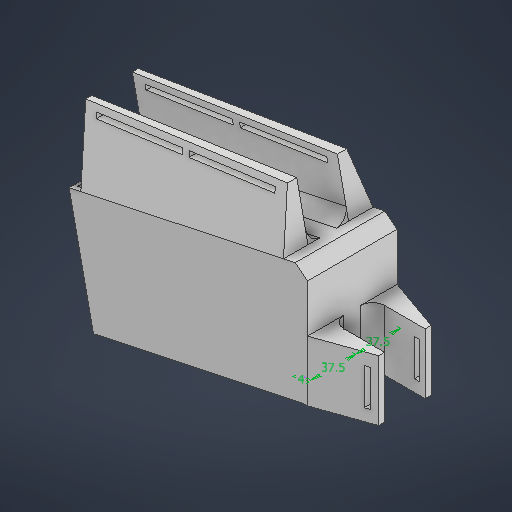
# Autodesk Inventor part: controllerholder
Saved by Autodesk Inventor 2026.3 (Build 303398000, 398)
## iProperties
Created: 2026-03-26
Part Number: controllerholder
Material: Generic
Document SubType Name: Modeling
Designer: runek
Density: 1 g/cm^3
Appearance: Default
Author: runek
Autodesk Inventor part; units mm, degrees
ref_plane "YZ Plane" through (0, 0, 0) normal (1, 0, 0) x (0, 1, 0)
ref_plane "XZ Plane" through (0, 0, 0) normal (0, 1, 0) x (-1, 0, 0)
ref_plane "XY Plane" through (0, 0, 0) normal (0, 0, 1) x (1, 0, 0)
sketch "Sketch1" plane through (0, 0, 0) normal (0, 1, 0) x (-1, 0, 0)
  line L0 (17.5, 0) -> (17.5, -37.5)
  line L1 (17.5, 0) -> (17.5, 37.5)
  line L2 (17.5, -37.5) -> (21.5, -37.5)
  line L3 (21.5, -37.5) -> (21.5, 37.5)
  line L4 (21.5, 37.5) -> (17.5, 37.5)
  line L5 (17.5, 37.5) -> (17.5, -37.5)
  point P0 (0, 0)
  point P1 (17.5, 37.5)
  dimension "d8" = 37.5
  dimension "d9" = 37.5
  dimension "d10" = 4
  constraints: 12 end point, 2 parallel, 1 horizontal, 1 perpendicular, 1 point on line, 1 vertical
  measures "d8" distance of L0.start L0.end
  measures "d9" distance of L0.start L1.end
  measures "d10" distance of L4.end L3.end
extrude "Extrusion2" add sketch "Sketch1" along normal blind 80
extrude "Extrusion3" add sketch "Sketch1" against normal blind 20
sketch "Sketch4" plane through (-17.5, 80, -37.5) normal (0, 0, -1) x (-1, 0, 0)
  line L0 (0, 0) -> (4, 0) projected
  line L1 (4, 0) -> (199.6295, -41.5823)
  line L2 (4, 0) -> (204, 0) construction
  line L3 (4, 0) -> (4, -4)
  line L4 (4, -4) -> (199.6295, -45.5823)
  line L5 (199.6295, -41.5823) -> (199.6295, -45.5823)
  line L6 (4, 0) -> (199.6295, -41.5823)
  line L7 (199.6295, -41.5823) -> (198.7979, -45.4949)
  line L8 (198.7979, -45.4949) -> (3.1684, -3.9126)
  line L9 (3.1684, -3.9126) -> (4, 0)
  line L10 (4, -100) -> (4, 0) projected
  line L11 (0, -100) -> (0, 0) projected
  line L12 (0, -9.3863) -> (10.3938, -1.3591)
  line L13 (0, -9.3863) -> (0, 0)
  line L14 (0, 0) -> (4, 0)
  line L15 (4, 0) -> (10.3938, -1.3591)
  line L16 (0, -9.3863) -> (10.3938, -1.3591)
  line L17 (10.3938, -1.3591) -> (12.8388, -4.5248)
  line L18 (12.8388, -4.5248) -> (2.445, -12.5521)
  line L19 (2.445, -12.5521) -> (0, -9.3863)
  point P0 (-17.5, -80)
  point P1 (198.816, -45.4094)
  point P2 (4, -11.3512)
  point P3 (11.3734, -5.6566)
  point P4 (6.2417, -4.5658)
  point P5 (4, -6.2971)
  point P6 (4, -4.0894)
  point P7 (6.3324, -4.4958)
  point P8 (10.3938, -1.3591)
  point P9 (11.4641, -5.5865)
  dimension "d20" = 200
  dimension "d21" = -12
  dimension "d22" = 4
  dimension "d23" = 200
  dimension "d24" = 102
  dimension "d48" = 4
  dimension "d49" = 4
  constraints: 34 end point, 5 parallel, 3 collinear, 3 perpendicular, 2 point on line, 1 equal length, 1 horizontal
  measures "d20" distance of L0.end L1.end
  measures "d21" angle of L2 L1
  measures "d22" distance of L0.end L3.end
  measures "d23" distance of L3.end L4.end
  measures "d24" angle of L4 L3
  measures "d48" distance of L1.end L7.end
  measures "d49" distance of L12.end L17.end
extrude "Extrusion5" add sketch "Sketch4" against normal blind 75 contours L1 L12 L4 L3 | L17 L18 L4 L12 | L1 L7 L4 L18 L17 | L12 L8 L18 L10 | L4 L18 L8 L12
extrude "Extrusion9" cut sketch "Sketch4" against normal blind 75 contours L0 L9 L8 L10 L12 L11 | L1 L12 L4 L3 | L3 L10 L8 L9
sketch "Sketch10" plane through (-27.8938, 78.6409, 37.5) normal (-0.2079117, 0.9781476, 0) x (0.9781476, 0.2079117, 0)
  line L0 (0, 75) -> (8.4977, 75) projected
  line L1 (0, 0) -> (-193.4633, 0) projected
  line L2 (0, 75) -> (0, 0)
  line L3 (0, 0) -> (-193.4633, 0)
  line L4 (-193.4633, 0) -> (-193.4633, 75)
  line L5 (-193.4633, 75) -> (0, 75)
  line L6 (-193.4633, 0) -> (-193.4633, 16.5)
  line L7 (-193.4633, 75) -> (-193.4633, 0) projected
  line L8 (-193.4633, 16.5) -> (-193.4633, 20.5)
  line L9 (-193.4633, 20.5) -> (-193.4633, 54.5)
  line L10 (-193.4633, 54.5) -> (-193.4633, 58.5)
  line L11 (-193.4633, 16.5) -> (0, 16.5)
  line L12 (0, 16.5) -> (0, 20.5)
  line L13 (0, 20.5) -> (-193.4633, 20.5)
  line L14 (-193.4633, 20.5) -> (-193.4633, 16.5)
  line L15 (-193.4633, 54.5) -> (-193.4633, 58.5)
  line L16 (-193.4633, 58.5) -> (0, 58.5)
  line L17 (0, 58.5) -> (0, 54.5)
  line L18 (0, 54.5) -> (-193.4633, 54.5)
  line L19 (0, 20.5) -> (-10, 20.5)
  line L20 (-10, 20.5) -> (-10, 16.5)
  line L21 (-193.4633, 16.5) -> (-183.4633, 16.5)
  line L22 (-183.4633, 16.5) -> (-183.4633, 20.5)
  line L23 (-193.4633, 54.5) -> (-183.4633, 54.5)
  line L24 (-183.4633, 54.5) -> (-183.4633, 58.5)
  line L25 (-193.4633, 75) -> (-183.4633, 75)
  line L26 (-183.4633, 75) -> (-183.4633, 0)
  line L27 (-183.4633, 0) -> (-193.4633, 0)
  line L28 (-193.4633, 0) -> (-193.4633, 75)
  line L29 (0, 0) -> (0, 75) projected
  line L30 (0, 0) -> (-4, 0)
  line L31 (-4, 0) -> (-4, 75)
  line L32 (-4, 75) -> (0, 75)
  line L33 (0, 75) -> (0, 0)
  line L34 (-14.2545, 75) -> (4.1766, 75) projected
  line L35 (0, 75) -> (-10, 75)
  line L36 (-10, 75) -> (-10, 0)
  line L37 (-10, 0) -> (0, 0)
  line L38 (0, 0) -> (0, 75)
  point P0 (10.9339, 37.5)
  point P1 (0, 54.5)
  point P2 (0, 58.5)
  point P3 (-10, 16.5)
  point P4 (-183.4633, 16.5)
  point P5 (-183.4633, 0)
  point P6 (-10, 75)
  point P7 (-183.4633, 58.5)
  point P8 (-10, 54.5)
  dimension "d52" = 16.5
  dimension "d53" = 4
  dimension "d54" = 34
  dimension "d55" = 4
  dimension "d56" = 4
  dimension "d57" = 10
  dimension "d58" = 10
  dimension "d64" = 10
  dimension "d65" = 4
  dimension "d66" = 75
  dimension "d67" = 75
  constraints: 68 end point, 16 point on line, 12 parallel, 10 perpendicular, 1 collinear
  measures "d52" distance of L3.end L6.end
  measures "d53" distance of L6.end L8.end
  measures "d54" distance of L8.end L9.end
  measures "d55" distance of L9.end L10.end
  measures "d56" distance of L12.end L11.end
  measures "d57" distance of L12.end L19.end
  measures "d58" distance of L6.end L21.end
  measures "d64" distance of L4.end L25.end
  measures "d65" distance of L1.start L30.end
  measures "d66" distance of L30.end L31.end
  measures "d67" distance of L36.end L35.end
extrude "Extrusion10" add sketch "Sketch10" along normal blind 55 contours L1 L26 L11 L36 | L11 L22 L13 L20 | L18 L24 L16 L36 | L16 L26 L5 L36
sketch "Sketch14" plane through (-17.5, -20, -37.5) normal (0, 0, -1) x (-1, 0, 0)
  line L0 (31.6105, 150.3599) -> (201.2832, 114.2949) projected
  line L1 (31.6105, 150.3599) -> (29.5313, 140.5785)
  line L2 (20.1753, 96.5618) -> (31.6105, 150.3599) projected
  line L3 (31.6105, 150.3599) -> (41.6105, 150.3599) construction
  line L4 (29.5313, 140.5785) -> (201.2832, 114.2949)
  line L5 (201.2832, 114.2949) -> (31.6105, 150.3599)
  line L6 (29.5313, 140.5785) -> (28.4918, 135.6877)
  line L7 (20.1753, 96.5618) -> (31.6105, 150.3599) projected
  line L8 (29.5313, 140.5785) -> (34.5313, 140.5785) construction
  line L9 (201.2832, 114.2949) -> (200.2436, 109.4042)
  line L10 (189.848, 60.4968) -> (201.2832, 114.2949) projected
  line L11 (201.2832, 114.2949) -> (206.2832, 114.2949) construction
  line L12 (200.2436, 109.4042) -> (28.4918, 135.6877)
  line L13 (28.4918, 135.6877) -> (27.6601, 131.7751)
  line L14 (28.4918, 135.6877) -> (32.4918, 135.6877) construction
  line L15 (200.2436, 109.4042) -> (199.412, 105.4916)
  line L16 (200.2436, 109.4042) -> (204.2436, 109.4042) construction
  line L17 (199.412, 105.4916) -> (27.6601, 131.7751)
  line L18 (28.4918, 135.6877) -> (38.3767, 134.175)
  line L19 (200.2436, 109.4042) -> (190.3587, 110.9169)
  line L20 (190.3587, 110.9169) -> (189.7546, 106.9695)
  line L21 (38.3767, 134.175) -> (37.7726, 130.2276)
  line L22 (38.3767, 134.175) -> (114.3675, 122.546)
  line L23 (114.3675, 122.546) -> (117.333, 122.0922)
  line L24 (117.333, 122.0922) -> (116.7289, 118.1447)
  line L25 (117.333, 122.0922) -> (111.4021, 122.9998)
  line L26 (111.4021, 122.9998) -> (110.798, 119.0524)
  line L27 (116.7289, 118.1447) -> (110.798, 119.0524)
  point P0 (-17.5, 20)
  dimension "d68" = 10
  dimension "d69" = 102
  dimension "d80" = 5
  dimension "d81" = 102
  dimension "d82" = 5
  dimension "d83" = 102
  dimension "d84" = 4
  dimension "d85" = 102
  dimension "d86" = 4
  dimension "d87" = 102
  dimension "d88" = 10
  dimension "d89" = 10
  dimension "d131" = 76.8755
  dimension "d132" = 3
  dimension "d133" = 6
  constraints: 48 end point, 9 point on line, 7 collinear, 5 equal length, 5 horizontal, 4 perpendicular
  measures "d68" distance of L0.start L1.end
  measures "d69" angle of L1 L3
  measures "d80" distance of L1.end L6.end
  measures "d81" angle of L6 L8
  measures "d82" distance of L0.end L9.end
  measures "d83" angle of L9 L11
  measures "d84" distance of L6.end L13.end
  measures "d85" angle of L13 L14
  measures "d86" distance of L9.end L15.end
  measures "d87" angle of L15 L16
  measures "d88" distance of L6.end L18.end
  measures "d89" distance of L9.end L19.end
  measures "d131" distance of L18.end L22.end
  measures "d132" distance of L22.end L23.end
  measures "d133" distance of L23.end L25.end
extrude "Extrusion12" cut sketch "Sketch14" against normal blind 75 contours L0 L4 L1 | L20 L17 L24 L12 | L12 L26 L17 L21
sketch "Sketch16" plane through (-207.348, 40.4968, -37.5) normal (-0.9781476, -0.2079117, 0) x (0, 0, 1)
  line L0 (20.5, 45) -> (20.5, 55) projected
  line L1 (20.5, 55) -> (15.5, 55)
  line L2 (0, 55) -> (20.5, 55) projected
  line L3 (0, 0) -> (0, 45) projected
  line L4 (15.5, 55) -> (0, 0)
  line L5 (0, 0) -> (0, 55)
  line L6 (0, 55) -> (15.5, 55)
  point P0 (37.5, -82.7219)
  dimension "d74" = 5
  constraints: 8 end point, 2 point on line, 1 collinear, 1 perpendicular
  measures "d74" distance of L0.end L1.end
extrude "Extrusion14" cut sketch "Sketch16" against normal blind 200
sketch "Sketch17" plane through (-207.348, 40.4968, 17) normal (-0.9781476, -0.2079117, 0) x (0, 0, 1)
  line L0 (0, 55) -> (20.5, 55) projected
  line L1 (0, 55) -> (5, 55)
  line L2 (5, 55) -> (20.5, 55)
  line L3 (20.5, 0) -> (0, 0) projected
  line L4 (20.5, 55) -> (20.5, 0)
  line L5 (5, 55) -> (20.5, 0)
  point P0 (-17, -82.7219)
  dimension "d77" = 5
  constraints: 8 end point, 1 collinear, 1 perpendicular, 1 point on line
  measures "d77" distance of L0.start L1.end
extrude "Extrusion15" cut sketch "Sketch17" against normal blind 200
sketch "Sketch18" plane through (-17.5, -20, 37.5) normal (1, 0, 0) x (0, 0, -1)
  line L0 (75, 0) -> (0, 0) projected
  line L1 (75, 90.6137) -> (0, 90.6137) projected
  line L2 (0, 0) -> (0, 90.6137)
  line L3 (0, 90.6137) -> (75, 90.6137)
  line L4 (75, 90.6137) -> (75, 0)
  line L5 (75, 0) -> (0, 0)
  line L6 (0, 90.6137) -> (0, 0) projected
  line L7 (0, 90.6137) -> (0, 50.6137)
  line L8 (0, 50.6137) -> (75, 50.6137)
  line L9 (75, 50.6137) -> (75, 90.6137)
  line L10 (75, 90.6137) -> (0, 90.6137)
  line L11 (0, 0) -> (16.5, 0)
  line L12 (16.5, 0) -> (20.5, 0)
  line L13 (20.5, 0) -> (54.5, 0)
  line L14 (54.5, 0) -> (58.5, 0)
  line L15 (20.5, 0) -> (20.5, 50.6137)
  line L16 (20.5, 50.6137) -> (0, 50.6137)
  line L17 (0, 50.6137) -> (0, 0)
  line L18 (0, 0) -> (20.5, 0)
  line L19 (75, 0) -> (75, 50.6137)
  line L20 (75, 50.6137) -> (54.5, 50.6137)
  line L21 (54.5, 50.6137) -> (54.5, 0)
  line L22 (54.5, 0) -> (75, 0)
  point P0 (37.5, 20)
  point P1 (75, 50.6137)
  point P2 (20.5, 0)
  point P3 (0, 50.6137)
  dimension "d90" = 40
  dimension "d91" = 16.5
  dimension "d92" = 4
  dimension "d93" = 34
  dimension "d94" = 4
  constraints: 40 end point, 8 parallel, 8 point on line, 6 perpendicular, 1 vertical
  measures "d90" distance of L1.end L7.end
  measures "d91" distance of L0.end L11.end
  measures "d92" distance of L11.end L12.end
  measures "d93" distance of L12.end L13.end
  measures "d94" distance of L13.end L14.end
extrude "Extrusion16" add sketch "Sketch18" along normal blind 44 contours L0 L21 L8 L4 | L0 L2 L8 L15
sketch "Sketch19" plane through (0, -20, 0) normal (0, -1, 0) x (1, 0, 0)
  line L0 (26.5, -37.5) -> (26.5, -17) projected
  line L1 (26.5, -17) -> (26.5, -22)
  line L2 (-17.5, -17) -> (-17.5, -37.5) projected
  line L3 (26.5, -22) -> (-17.5, -37.5)
  line L4 (-17.5, -37.5) -> (26.5, -37.5)
  line L5 (26.5, -37.5) -> (26.5, -22)
  line L6 (-21.5, 37.5) -> (-21.5, -37.5) projected
  line L7 (-21.5, 0) -> (30.778, 0)
  line L8 (26.5, 37.5) -> (26.5, 17)
  line L9 (26.5, 22) -> (-17.5, 37.5)
  line L10 (-17.5, 37.5) -> (26.5, 37.5)
  point P0 (0, 0)
  dimension "d97" = 5
  constraints: 16 end point, 5 symmetric about line, 3 point on line, 2 perpendicular, 1 horizontal, 1 midpoint
  measures "d97" distance of L0.end L1.end
sketch "Sketch20" plane through (-21.5, -20, 37.5) normal (0, 0, 1) x (1, 0, 0)
  line L0 (0, 0) -> (48, 0) projected
  line L1 (4, 50.6137) -> (48, 50.6137) projected
  line L2 (48, 0) -> (48, 50.6137)
  line L3 (48, 50.6137) -> (43, 50.6137)
  line L4 (43, 50.6137) -> (43, 0)
  line L5 (43, 0) -> (48, 0)
  line L6 (43, 50.6137) -> (43, 0)
  line L7 (43, 0) -> (39, 0)
  line L8 (39, 0) -> (39, 50.6137)
  line L9 (39, 50.6137) -> (43, 50.6137)
  line L10 (39, 50.6137) -> (39, 40.6137)
  line L11 (39, 40.6137) -> (43, 40.6137)
  line L12 (43, 40.6137) -> (43, 50.6137)
  line L13 (43, 50.6137) -> (39, 50.6137)
  line L14 (39, 0) -> (39, 10)
  line L15 (39, 10) -> (43, 10)
  line L16 (43, 10) -> (43, 0)
  line L17 (43, 0) -> (39, 0)
  point P0 (21.5, 20)
  point P1 (43, 10)
  dimension "d98" = 5
  dimension "d99" = 4
  dimension "d100" = 10
  dimension "d101" = 10
  dimension "d102" = 4
  constraints: 32 end point, 9 equal length, 4 perpendicular, 2 point on line, 1 vertical
  measures "d98" distance of L3.end L1.end
  measures "d99" distance of L4.end L7.end
  measures "d100" distance of L8.end L10.end
  measures "d101" distance of L7.end L14.end
  measures "d102" distance of L14.end L15.end
extrude "Extrusion17" cut sketch "Sketch20" against normal blind 75 contours L8 L11 L4 L15
extrude "Extrusion18" cut sketch "Sketch19" against normal blind 75
sketch "Sketch21" plane through (-21.5, -20, 37.5) normal (0, 0, 1) x (1, 0, 0)
  line L0 (0, 0) -> (0, 88.6488) projected
  line L1 (0, 0) -> (-200, 0)
  line L2 (-7.4641, 94.4135) -> (-194.816, 54.5906) projected
  line L3 (-194.816, 54.5906) -> (-183.2125, 0)
  line L4 (-194.816, 54.5906) -> (-195.6295, 58.4177) projected
  line L5 (0, 0) -> (-175.2927, -37.2596)
  line L6 (-175.2927, -37.2596) -> (-183.2125, 0)
  line L7 (0, 88.6488) -> (-7.4641, 94.4135) projected
  line L8 (0, 88.6488) -> (-7.4641, 94.4135)
  point P0 (21.5, 20)
  dimension "d107" = 200
  constraints: 10 end point, 3 collinear, 2 point on line, 1 horizontal, 1 perpendicular
  measures "d107" distance of L0.start L1.end
extrude "Extrusion19" add sketch "Sketch21" against normal blind 4
sketch "Sketch22" plane through (-21.5, -20, 33.5) normal (0, 0, -1) x (-1, 0, 0)
  line L0 (175.2927, -37.2596) -> (0, 0) projected
  line L1 (0, 0) -> (175.2927, -37.2596) projected
  line L2 (175.2927, -37.2596) -> (0, 0)
  line L3 (175.2927, -37.2596) -> (176.1243, -33.347)
  line L4 (175.2927, -37.2596) -> (194.816, 54.5906) projected
  line L5 (0, 0) -> (0, 4)
  line L6 (0, 0) -> (0, 88.6488) projected
  line L7 (176.1243, -33.347) -> (0, 4)
  point P0 (-21.5, 20)
  dimension "d110" = 4
  dimension "d111" = 4
  constraints: 8 end point, 2 point on line, 1 collinear
  measures "d110" distance of L0.start L3.end
  measures "d111" distance of L0.end L5.end
extrude "Extrusion20" add sketch "Sketch22" along normal blind 71
sketch "Sketch23" plane through (-17.5, -20, -37.5) normal (0, 0, -1) x (-1, 0, 0)
  line L0 (199.6295, 58.4177) -> (189.848, 60.4968) projected
  line L1 (199.6295, 58.4177) -> (179.2927, -37.2596)
  line L2 (4, 0) -> (0, 0) projected
  line L3 (179.2927, -37.2596) -> (4, 0)
  line L4 (4, 0) -> (4, 88.6665)
  line L5 (4, 88.6665) -> (11.4641, 94.4135)
  line L6 (11.4641, 94.4135) -> (199.6295, 58.4177)
  point P0 (-17.5, 20)
  constraints: 10 end point, 2 perpendicular
extrude "Extrusion21" add sketch "Sketch23" against normal blind 4
sketch "Sketch24" plane through (-27.8938, 78.6409, 37.5) normal (-0.2079117, 0.9781476, 0) x (0.9781476, 0.2079117, 0)
  line L0 (-183.4633, 54.5) -> (-183.4633, 75) projected
  line L1 (-183.4633, 0) -> (-183.4633, 15.5) projected
  line L2 (-183.4633, 75) -> (-183.4633, 0)
  line L3 (-183.4633, 0) -> (-193.4633, 0)
  line L4 (-193.4633, 0) -> (-193.4633, 75)
  line L5 (-193.4633, 75) -> (-183.4633, 75)
  line L6 (-193.4633, 75) -> (-183.4633, 75) projected
  line L7 (-193.4633, 75) -> (-190.1633, 75)
  line L8 (-190.1633, 75) -> (-186.7633, 75)
  line L9 (-190.1633, 75) -> (-186.7633, 75)
  line L10 (-186.7633, 75) -> (-186.7633, 0)
  line L11 (-186.7633, 0) -> (-190.1633, 0)
  line L12 (-190.1633, 0) -> (-190.1633, 75)
  line L13 (-190.1633, 75) -> (-186.7633, 75)
  line L14 (-186.7633, 75) -> (-186.7633, 71)
  line L15 (-186.7633, 71) -> (-190.1633, 71)
  line L16 (-190.1633, 71) -> (-190.1633, 75)
  line L17 (-186.7633, 0) -> (-190.1633, 0)
  line L18 (-190.1633, 0) -> (-190.1633, 4)
  line L19 (-190.1633, 4) -> (-186.7633, 4)
  line L20 (-186.7633, 4) -> (-186.7633, 0)
  point P0 (10.9339, 37.5)
  point P1 (-190.1633, 4)
  point P2 (-186.7633, 4)
  point P3 (-186.7633, 71)
  point P4 (-190.1633, 71)
  dimension "d116" = 3.3
  dimension "d117" = 3.4
  dimension "d118" = 4
  dimension "d119" = 4
  constraints: 36 end point, 8 parallel, 4 perpendicular, 3 collinear, 2 point on line, 1 vertical
  measures "d116" distance of L4.end L7.end
  measures "d117" distance of L7.end L8.end
  measures "d118" distance of L8.end L14.end
  measures "d119" distance of L11.end L18.end
extrude "Extrusion22" cut sketch "Sketch24" against normal blind 4 contours L10 L19 L12 L15
sketch "Sketch25" plane through (-207.348, 40.4968, 17) normal (-0.9781476, -0.2079117, 0) x (0, 0, 1)
  line L0 (0, 0) -> (0, 55) projected
  line L1 (0, 0) -> (0, 10)
  line L2 (0, 0) -> (-10, 0)
  line L3 (-54.5, 0) -> (20.5, 0) projected
  arc A0 (-10, 0) -> (0, 10) centre (-10.7232, 10.7232) ccw
  line L4 (-34, 0) -> (-17, 0)
  line L5 (-17, 0) -> (-17, 22.6704)
  line L6 (-34, 0) -> (-34, 10)
  line L7 (-34, 0) -> (-24, 0)
  arc A1 (-34, 10) -> (-24, 0) centre (-23.2768, 10.7232) ccw
  point P0 (-17, -82.7219)
  point P1 (-24, 0)
  dimension "d122" = 10
  dimension "d123" = 10
  dimension "d124" = 17
  constraints: 12 end point, 4 point on circle, 3 symmetric about line, 2 centre point, 2 point on line, 1 midpoint, 1 perpendicular, 1 other
  measures "d122" distance of L0.start L1.end
  measures "d123" distance of L0.start L2.end
  measures "d124" distance of L4.start L4.end
extrude "Extrusion23" add sketch "Sketch25" against normal blind 173.5
sketch "Sketch26" plane through (-17.5, 30.6137, 17) normal (0, 1, 0) x (1, 0, 0)
  line L0 (0, 0) -> (44, 0) projected
  line L1 (0, 0) -> (10, 0)
  line L2 (0, 34) -> (0, 0) projected
  line L3 (0, 0) -> (0, 10)
  arc A0 (0, 10) -> (10, 0) centre (10, 10) ccw
  line L4 (0, 17) -> (44, 17)
  line L5 (0, 34) -> (44, 34)
  line L6 (0, 0) -> (0, 34)
  arc A1 (10, 34) -> (0, 24) centre (10, 24) ccw
  point P0 (17.5, 17)
  point P1 (0, 34)
  point P2 (0, 24)
  dimension "d127" = 10
  dimension "d128" = 10
  constraints: 10 end point, 6 symmetric about line, 4 point on circle, 4 point on line, 2 centre point, 1 horizontal, 1 midpoint, 1 tangent, 1 other
  measures "d127" distance of L0.start L1.end
  measures "d128" distance of L0.start L3.end
extrude "Extrusion24" add sketch "Sketch26" against normal blind 50.6
sketch "Sketch32" plane through (-21.5, -20, 33.5) normal (0, 0, -1) x (-1, 0, 0)
  line L0 (191.5882, 55.2767) -> (194.816, 54.5906) projected
  line L1 (191.5882, 55.2767) -> (194.8488, 54.5836)
  line L2 (194.8488, 54.5836) -> (182.3741, -4.1052)
  line L3 (182.3741, -4.1052) -> (179.1135, -3.4122)
  line L4 (179.1135, -3.4122) -> (191.5882, 55.2767)
  line L5 (192.4016, 59.1038) -> (191.5882, 55.2767) projected
  line L6 (7.4641, 94.4135) -> (188.2625, 55.9836) projected
  line L7 (188.2625, 55.9836) -> (185.0346, 56.6697)
  line L8 (185.0346, 56.6697) -> (172.5599, -2.0192)
  line L9 (172.5599, -2.0192) -> (175.7878, -2.7053)
  line L10 (175.7878, -2.7053) -> (188.2625, 55.9836)
  line L11 (175.7878, -2.7053) -> (179.1135, -3.4122)
  line L12 (179.1135, -3.4122) -> (180.153, 1.4786)
  line L13 (180.153, 1.4786) -> (176.8273, 2.1855)
  line L14 (176.8273, 2.1855) -> (175.7878, -2.7053)
  point P0 (-21.5, 20)
  point P1 (180.153, 1.4786)
  dimension "d134" = 60
  dimension "d137" = 3.2279
  dimension "d138" = 3.3
  dimension "d139" = 60
  dimension "d140" = 5
  constraints: 24 end point, 6 parallel, 4 perpendicular, 1 point on line
  measures "d134" distance of L1.end L2.end
  measures "d137" horizontal distance of L0.start L0.end
  measures "d138" distance of L6.end L7.end
  measures "d139" distance of L8.end L7.end
  measures "d140" distance of L12.end L3.end
extrude "Extrusion25" add sketch "Sketch32" along normal blind 5
sketch "Sketch33" plane through (-17.5, -20, -33.5) normal (0, 0, 1) x (1, 0, 0)
  line L0 (-198.816, 54.5906) -> (-195.5882, 55.2767) projected
  line L1 (-195.5882, 55.2767) -> (-198.816, 54.5906)
  line L2 (-198.816, 54.5906) -> (-186.3413, -4.0983)
  line L3 (-186.3413, -4.0983) -> (-183.1135, -3.4122)
  line L4 (-183.1135, -3.4122) -> (-195.5882, 55.2767)
  line L5 (-192.2625, 55.9836) -> (-189.0346, 56.6697)
  line L6 (-189.0346, 56.6697) -> (-176.5599, -2.0192)
  line L7 (-176.5599, -2.0192) -> (-179.7878, -2.7053)
  line L8 (-179.7878, -2.7053) -> (-192.2625, 55.9836)
  line L9 (-183.1135, -3.4122) -> (-179.7878, -2.7053)
  line L10 (-179.7878, -2.7053) -> (-180.8273, 2.1855)
  line L11 (-180.8273, 2.1855) -> (-184.153, 1.4786)
  line L12 (-184.153, 1.4786) -> (-183.1135, -3.4122)
  point P0 (17.5, 20)
  point P1 (-180.8273, 2.1855)
  point P2 (-184.153, 1.4786)
  dimension "d141" = 60
  dimension "d142" = 3.3
  dimension "d143" = 60
  dimension "d144" = 5
  constraints: 24 end point, 7 equal length, 3 perpendicular, 1 point on line
  measures "d141" distance of L2.end L0.start
  measures "d142" distance of L5.start L5.end
  measures "d143" distance of L5.end L6.end
  measures "d144" distance of L10.end L7.end
extrude "Extrusion26" add sketch "Sketch33" along normal blind 5
body "Solid1"
